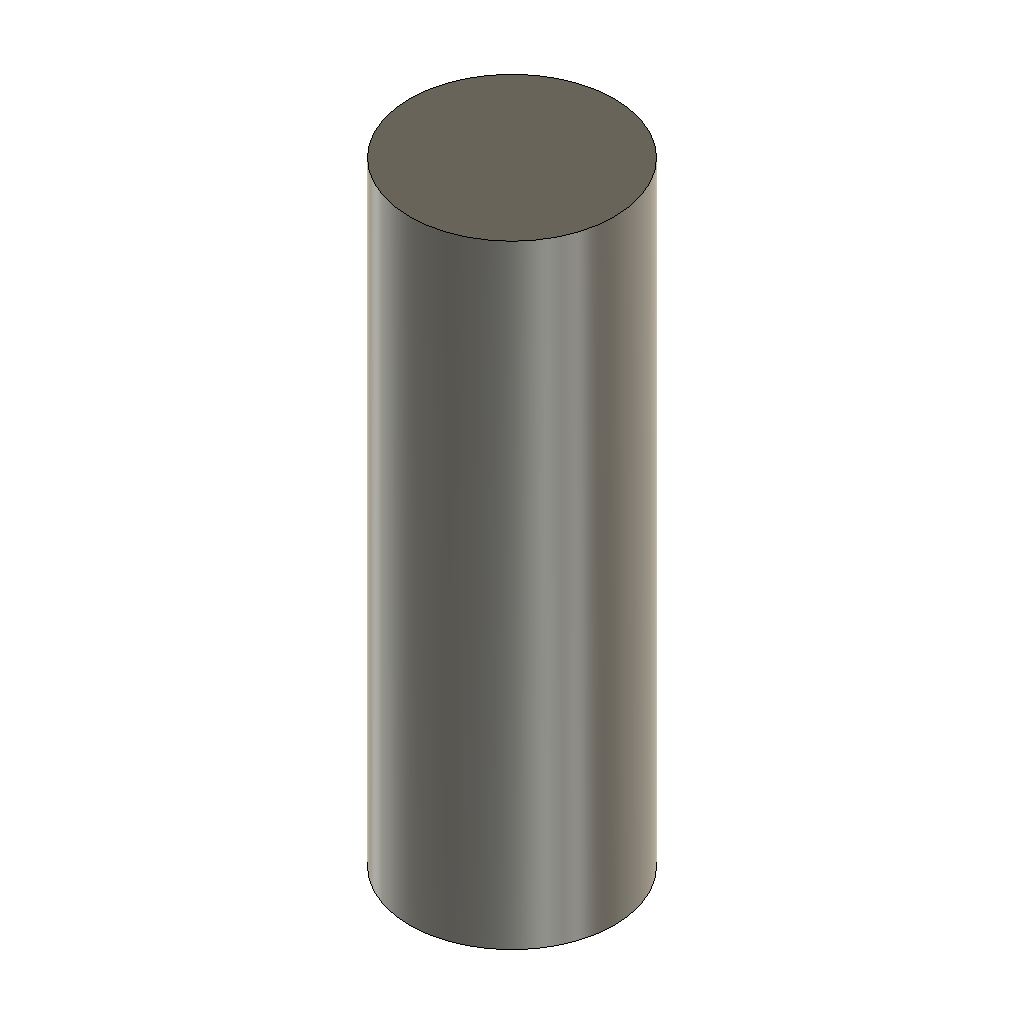
f2sc-test-insert-joint (Autodesk Fusion 360 archive; units mm, degrees)
design "f2sc-test-insert-part"
part number: 2026-11-27-12-51-19-991
Autodesk Fusion 360 part; units mm, degrees
sketch "Sketch1" plane through (0, 0, 0) normal (0, 0, 1) x (1, 0, 0)
  circle A0 centre (0, 0) radius 5
  dimension "d1" = 10
  constraint coincident A0.centre origin
  measures "d1" diameter of A0
extrude "Extrude1" add sketch "Sketch1" along normal blind 30
